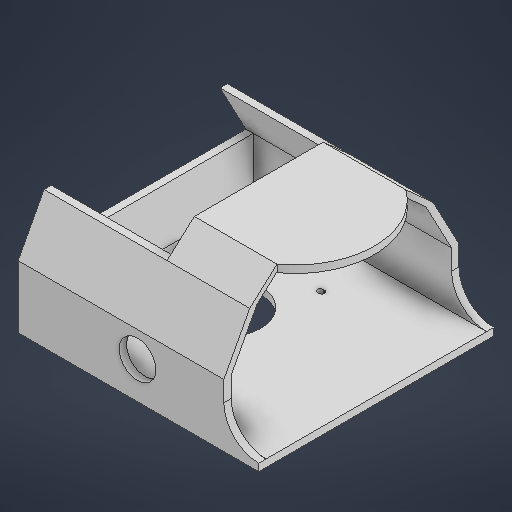
# Autodesk Inventor part: support_camacou
Saved by Autodesk Inventor 2026.1 (Build 301233020, 233B)
## iProperties
Created: 2026-10-27
Part Number: support_camacou
Material: Generic
Document SubType Name: Modeling
Designer: matar
Density: 1 g/cm^3
Appearance: Default
Author: matar
Autodesk Inventor part; units mm, degrees
ref_plane "YZ Plane" through (0, 0, 0) normal (1, 0, 0) x (0, 1, 0)
ref_plane "XZ Plane" through (0, 0, 0) normal (0, 1, 0) x (-1, 0, 0)
ref_plane "XY Plane" through (0, 0, 0) normal (0, 0, 1) x (1, 0, 0)
sketch "Sketch1" plane through (0, 0, 0) normal (0, 1, 0) x (-1, 0, 0)
  line L0 (0, 0) -> (127, 0)
  line L1 (127, 0) -> (127, -128)
  line L2 (127, -128) -> (0, -128)
  line L3 (0, -128) -> (0, 0)
  dimension "d0" = 128
  dimension "d1" = 127
  constraints: 8 end point, 2 parallel, 1 horizontal, 1 perpendicular
  measures "d0" distance of L0.end L1.end
  measures "d1" distance of L1.end L2.end
extrude "Extrusion1" add sketch "Sketch1" along normal blind 4
sketch "Sketch4" plane through (0, 4, 0) normal (0, 1, 0) x (1, 0, 0)
  line L0 (-127, 0) -> (0, 0) projected
  line L1 (-127, 128) -> (-127, 0) projected
  line L2 (0, 0) -> (-127, 0)
  line L3 (-127, 0) -> (-127, 4)
  line L4 (-127, 4) -> (0, 4)
  line L5 (0, 4) -> (0, 0)
  line L6 (0, 128) -> (-127, 128) projected
  line L7 (0, 128) -> (-127, 128)
  line L8 (-127, 128) -> (-127, 124)
  line L9 (-127, 124) -> (0, 124)
  line L10 (0, 124) -> (0, 128)
  point P0 (-127, 124)
  dimension "d7" = 4
  dimension "d8" = 4
  constraints: 16 end point, 4 parallel, 2 horizontal, 2 perpendicular, 2 point on line
  measures "d7" distance between parallel lines of L0 L4
  measures "d8" distance between parallel lines of L6 L9
extrude "Extrusion3" add sketch "Sketch4" along normal blind 30
sketch "Sketch6" plane through (0, 4, 0) normal (0, 1, 0) x (1, 0, 0)
  line L0 (-112.5, 30) -> (-113.5, 30) construction
  line L1 (-112.5, 31.5) -> (-113.5, 31.5)
  line L2 (-113.5, 28.5) -> (-112.5, 28.5)
  arc A0 (-112.5, 28.5) -> (-112.5, 31.5) centre (-112.5, 30) ccw
  arc A1 (-113.5, 31.5) -> (-113.5, 28.5) centre (-113.5, 30) ccw
  line L3 (-112.5, 98) -> (-113.5, 98) construction
  line L4 (-112.5, 99.5) -> (-113.5, 99.5)
  line L5 (-113.5, 96.5) -> (-112.5, 96.5)
  arc A2 (-112.5, 96.5) -> (-112.5, 99.5) centre (-112.5, 98) ccw
  arc A3 (-113.5, 99.5) -> (-113.5, 96.5) centre (-113.5, 98) ccw
  line L6 (-63.5, 98) -> (-64.5, 98) construction
  line L7 (-63.5, 99.5) -> (-64.5, 99.5)
  line L8 (-64.5, 96.5) -> (-63.5, 96.5)
  arc A4 (-63.5, 96.5) -> (-63.5, 99.5) centre (-63.5, 98) ccw
  arc A5 (-64.5, 99.5) -> (-64.5, 96.5) centre (-64.5, 98) ccw
  line L9 (-63.5, 30) -> (-64.5, 30) construction
  line L10 (-63.5, 31.5) -> (-64.5, 31.5)
  line L11 (-64.5, 28.5) -> (-63.5, 28.5)
  arc A6 (-63.5, 28.5) -> (-63.5, 31.5) centre (-63.5, 30) ccw
  arc A7 (-64.5, 31.5) -> (-64.5, 28.5) centre (-64.5, 30) ccw
  line L12 (-127, 4) -> (0, 4) projected
  line L13 (0, 4) -> (0, 124) projected
  point P0 (0, 0)
  point P1 (-113, 30)
  point P2 (-113, 98)
  point P3 (-64, 98)
  point P4 (-64, 30)
  point P5 (-62, 30)
  point P6 (-115, 30)
  point P7 (-115, 98)
  point P8 (-62, 98)
  point P9 (-64, 28.5)
  point P10 (-111, 30)
  point P11 (-66, 30)
  point P12 (-111, 98)
  point P13 (-66, 98)
  dimension "d14" = 71
  dimension "d15" = 71
  dimension "d16" = 53
  dimension "d17" = 53
  dimension "d18" = 3
  dimension "d19" = 3
  dimension "d20" = 3
  dimension "d21" = 3
  dimension "d22" = 4
  dimension "d23" = 4
  dimension "d24" = 4
  dimension "d25" = 4
  dimension "d26" = 24.5
  dimension "d27" = 24.5
  dimension "d28" = 62
  dimension "d29" = 62
  constraints: 32 end point, 24 point on circle, 16 tangent, 8 centre point, 5 midpoint, 4 horizontal, 4 parallel
  measures "d14" distance between parallel lines of L11 L7
  measures "d15" distance between parallel lines of L4 L2
  measures "d16" distance of point (-62, 30) point (-115, 30)
  measures "d17" distance of point (-115, 98) point (-62, 98)
  measures "d18" distance between parallel lines of L1 L2
  measures "d19" distance from line of L10 point (-64, 28.5)
  measures "d20" distance between parallel lines of L5 L4
  measures "d21" distance between parallel lines of L8 L7
  measures "d22" distance of point (-111, 30) point (-115, 30)
  measures "d23" distance of point (-66, 30) point (-62, 30)
  measures "d24" distance of point (-115, 98) point (-111, 98)
  measures "d25" distance of point (-66, 98) point (-62, 98)
  measures "d26" distance between parallel lines of L2 L12
  measures "d27" distance between parallel lines of L12 L11
  measures "d28" distance from line of L13 point (-62, 30)
  measures "d29" distance from line of L13 point (-62, 98)
extrude "Extrusion5" cut sketch "Sketch6" against normal through all
sketch "Sketch7" plane through (0, 4, 0) normal (0, 1, 0) x (1, 0, 0)
  circle A0 centre (-83, 64) radius 20
  line L0 (0, 4) -> (-127, 4) projected
  line L1 (-127, 124) -> (-127, 4) projected
  line L2 (-113.5, 31.5) -> (-112.5, 31.5) projected
  point P0 (0, 0)
  point P1 (-60, 4)
  dimension "d32" = 40
  dimension "d36" = 44
  dimension "d37" = 60
  constraints: 1 centre point
  measures "d32" diameter of A0
  measures "d36" distance from line of A0.centre L1
  measures "d37" distance from line of A0.centre L0
extrude "Extrusion6" cut sketch "Sketch7" against normal through all
sketch "Sketch9" plane through (0, 0, 0) normal (1, 0, 0) x (0, 0, -1)
  line L0 (4, 34) -> (4, 24) projected
  line L1 (4, 34) -> (18.0841, 60.4884)
  line L2 (18.0841, 60.4884) -> (14.0841, 60.4884)
  line L3 (0, 34) -> (4, 34) projected
  line L4 (14.0841, 60.4884) -> (0, 34)
  line L5 (124, 34) -> (128, 34) projected
  line L6 (128, 34) -> (113.9159, 60.4884)
  line L7 (113.9159, 60.4884) -> (109.9159, 60.4884)
  line L8 (124, 24) -> (124, 34) projected
  line L9 (109.9159, 60.4884) -> (124, 34)
  line L10 (124, 4) -> (124, 34) projected
  line L11 (4, 4) -> (4, 34) projected
  point P0 (0, 0)
  dimension "d41" = 4
  dimension "d43" = 4
  dimension "d45" = 152
  dimension "d46" = 152
  dimension "d48" = 30
  dimension "d49" = 30
  constraints: 12 end point, 1 parallel, 1 perpendicular
  measures "d41" distance of L1.end L2.end
  measures "d43" distance of L6.end L7.end
  measures "d45" angle of L9 L10
  measures "d46" angle of L1 L11
  measures "d48" distance of L7.end L5.start
  measures "d49" distance of L0.start L1.end
extrude "Extrusion7" add sketch "Sketch9" against normal blind 131
sketch "Sketch11" plane through (0, 0, 0) normal (1, 0, 0) x (0, 0, -1)
  line L0 (0, 34) -> (14.0841, 60.4884) projected
  line L1 (14.0841, 60.4884) -> (18.0841, 60.4884) projected
  line L2 (14.0841, 60.4884) -> (18.0841, 60.4884)
  line L3 (4, 4) -> (4, 34) projected
  line L4 (18.0841, 60.4884) -> (4, 34)
  line L5 (4, 34) -> (4, 4)
  line L6 (4, 4) -> (0, 4)
  line L7 (0, 0) -> (0, 34) projected
  line L8 (0, 34) -> (14.0841, 60.4884)
  line L9 (109.9159, 60.4884) -> (113.9159, 60.4884)
  line L10 (128, 34) -> (113.9159, 60.4884) projected
  line L11 (113.9159, 60.4884) -> (128, 34)
  line L12 (128, 34) -> (128, 4)
  line L13 (4, 4) -> (124, 4) projected
  line L14 (124, 4) -> (124, 34) projected
  line L15 (124, 4) -> (124, 34)
  line L16 (124, 34) -> (109.9159, 60.4884)
  line L17 (124, 4) -> (128, 4)
  constraints: 22 end point, 5 equal length, 1 horizontal, 1 perpendicular, 1 point on line, 1 vertical
extrude "Extrusion8" cut sketch "Sketch11" against normal blind 19
sketch "Sketch14" plane through (-127, 0, 0) normal (0, 0, 1) x (1, 0, 0)
  line L0 (108, 34) -> (108, 4) projected
  line L1 (108, 4) -> (127, 4) projected
  arc A0 (108, 23) -> (127, 4) centre (127, 23) ccw
  point P0 (127, 0)
  dimension "d57" = 19
  constraints: 2 point on circle, 1 centre point, 1 point on line
  measures "d57" radius of A0
extrude "Extrusion9" add sketch "Sketch14" against normal blind 4
sketch "Sketch17" plane through (0, 0, -128) normal (0, 0, -1) x (-1, 0, 0)
  line L0 (127, 4) -> (0, 4) projected
  arc A0 (0, 4) -> (19, 23) centre (0, 23) ccw
  line L1 (19, 34) -> (19, 4) projected
  point P0 (0, 0)
  dimension "d63" = 19
  dimension "d64" = 0
  constraints: 2 point on circle, 1 centre point
  measures "d63" radius of A0
  measures "d64" distance from line of L1 A0.end
extrude "Extrusion10" add sketch "Sketch17" against normal blind 4
sketch "Sketch18" plane through (-19, 0, 0) normal (1, 0, 0) x (0, 0, -1)
  line L0 (18.0841, 60.4884) -> (4, 34) projected
  line L1 (18.0841, 60.4884) -> (32.947, 73.871)
  line L2 (32.947, 73.871) -> (28.947, 73.871)
  line L3 (14.0841, 60.4884) -> (18.0841, 60.4884) projected
  line L4 (28.947, 73.871) -> (14.0841, 60.4884)
  line L5 (109.9159, 60.4884) -> (113.9159, 60.4884) projected
  line L6 (113.9159, 60.4884) -> (99.053, 73.871)
  line L7 (99.053, 73.871) -> (95.053, 73.871)
  line L8 (109.9159, 60.4884) -> (95.053, 73.871)
  line L9 (124, 34) -> (109.9159, 60.4884) projected
  point P0 (0, 0)
  dimension "d67" = 4
  dimension "d68" = 20
  dimension "d69" = 160
  dimension "d70" = 20
  dimension "d71" = 4
  dimension "d72" = 160
  constraints: 12 end point, 1 horizontal, 1 parallel
  measures "d67" distance of L1.end L2.end
  measures "d68" distance of L0.start L1.end
  measures "d69" angle of L1 L0
  measures "d70" distance of L5.start L7.end
  measures "d71" distance of L6.end L7.end
  measures "d72" angle of L8 L9
extrude "Extrusion11" add sketch "Sketch18" against normal blind 45
sketch "Sketch19" plane through (-19, 73.871, -95.053) normal (0, 1, 0) x (1, 0, 0)
  arc A0 (0, -66.1059) -> (0, 4) centre (-25.1308, -31.053) ccw
  line L0 (0, 4) -> (-45, 4) projected
  line L1 (-45, 4) -> (-45, -66.1059)
  line L2 (0, 4) -> (-45, 4)
  line L3 (0, -66.1059) -> (-45, -66.1059)
  line L4 (0, -62.1059) -> (0, -66.1059) projected
  point P0 (19, -95.053)
  constraints: 6 end point, 2 point on circle, 1 centre point, 1 collinear, 1 perpendicular
extrude "Extrusion12" add sketch "Sketch19" against normal blind 4
sketch "Sketch21" plane through (-127, 0, -128) normal (-1, 0, 0) x (0, 0, 1)
  line L0 (128, 0) -> (128, 34) projected
  line L1 (0, 0) -> (0, 34) projected
  line L2 (128, 0) -> (0, 0)
  line L3 (0, 0) -> (0, 34)
  line L4 (0, 34) -> (128, 34)
  line L5 (128, 34) -> (128, 0)
  constraints: 8 end point, 2 parallel, 1 horizontal, 1 perpendicular
extrude "Extrusion14" add sketch "Sketch21" along normal blind 4
sketch "Sketch22" plane through (-131, 0, 0) normal (0, 0, 1) x (1, 0, 0)
  circle A0 centre (65, 20) radius 10
  line L0 (0, 0) -> (0, 34) projected
  line L1 (131, 0) -> (0, 0) projected
  dimension "d82" = 65
  dimension "d83" = 20
  dimension "d86" = 20
  constraints: 1 centre point
  measures "d82" distance from line of L0 A0.centre
  measures "d83" distance from line of L1 A0.centre
  measures "d86" diameter of A0
extrude "Extrusion15" cut sketch "Sketch22" against normal blind 10
body "Solid1"
